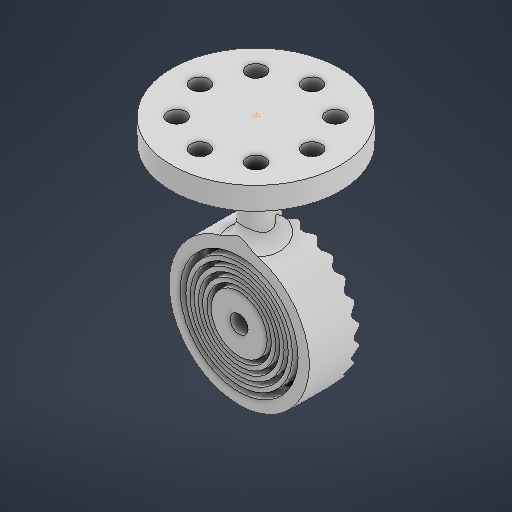
# Autodesk Inventor part: ParteA
Saved by Autodesk Inventor 2027.1 (Build 311270010, 270A)
## iProperties
Created: 2026-09-14
Part Number: ParteA
Material: Genérico
Document SubType Name: Modeling
Designer: felip
Density: 1 g/cm^3
Appearance: Valor por defecto
Author: felip
Autodesk Inventor part; units mm, degrees
sketch "Boceto1" plane through (0, 0, 0) normal (0, 0, 1) x (1, 0, 0)
  circle A0 centre (0, 0) radius 25
  circle A1 centre (0, 0) radius 3.175
  dimension "d0" = 50
  dimension "d1" = 6.35
  constraints: 2 centre point, 2 coincident
  measures "d0" diameter of A0
  measures "d1" diameter of A1
extrude "Extrusión1" add sketch "Boceto1" along normal blind 12 and the other way blind 6
ref_plane "Plano de trabajo1" through (0, 25, 0) normal (0, 1, 0) x (-1, 0, 0)
sketch "Boceto3" plane through (0, 25, 0) normal (0, 1, 0) x (-1, 0, 0)
  line L0 (3.175, -6) -> (-3.175, -6) projected
  line L1 (2.784, -6) -> (-2.784, -6)
  line L2 (0, -6) -> (0, -4) construction
  line L3 (0.5, -4) -> (-0.5, -4)
  line L4 (2.784, -6) -> (0.5, -4)
  line L5 (-0.5, -4) -> (-2.784, -6)
  point P0 (0, 0)
  dimension "d16" = 5.568
  dimension "d17" = 2
  dimension "d18" = 1
  constraints: 10 end point, 3 midpoint, 1 horizontal, 1 point on line, 1 vertical
  measures "d16" distance of L1.start L1.end
  measures "d17" distance of L2.start L2.end
  measures "d18" distance of L3.start L3.end
loft "Solevación2" cut profiles "Boceto3" section 2 point at (0, 0, -6)
ref_plane "Plano de trabajo3" through (0, 3.1, 0) normal (0, 1, 0) x (-1, 0, 0)
sketch "Boceto6" plane through (0, 3.1, 0) normal (0, 1, 0) x (-1, 0, 0)
  line L0 (0.3514, -6) -> (-0.3514, -6)
  line L1 (0, -6) -> (0, -4) construction
  line L2 (0.0635, -4) -> (-0.0635, -4)
  line L3 (0.3514, -6) -> (0.0635, -4)
  line L4 (-0.0635, -4) -> (-0.3514, -6)
  point P0 (0, 0)
  point P1 (0, -6)
  point P2 (0.0635, -5.7461)
  dimension "d48" = 2
  dimension "d49" = 0.127
  constraints: 10 end point, 2 midpoint, 1 vertical
  measures "d48" distance of L1.start L1.end
  measures "d49" distance of L2.start L2.end
loft "Solevación4" cut profiles "Boceto3", "Boceto6"
pattern_circular "Patrón circular4" count 24 over 360 about axis through (0, 0, 0) along (0, 0, 1) of "Solevación4"
ref_plane "Plano de trabajo4" through (0, 0, 6) normal (0, 0, 1) x (1, 0, 0)
sketch "Boceto8" plane through (0, 0, 6) normal (0, 0, 1) x (1, 0, 0)
  line L0 (0, 0) -> (0, 20)
  line L1 (0, 20) -> (0, 45)
  dimension "d63" = 20
  dimension "d64" = 25
  constraints: 4 end point, 1 point on line, 1 vertical
  measures "d63" distance of L0.start L0.end
  measures "d64" distance of L0.end L1.end
sketch "Boceto9" plane through (0, 0, 0) normal (0, 1, 0) x (-1, 0, 0)
  line L0 (0, 0) -> (0, 6) construction
  circle A0 centre (0, 6) radius 5
  dimension "d65" = 6
  dimension "d66" = 10
  constraints: 2 end point, 1 centre point, 1 coincident, 1 vertical
  measures "d65" distance of L0.start L0.end
  measures "d66" diameter of A0
sweep "Barrido1" add profiles "Boceto9" path "Boceto8"
fillet "Empalme1" radius 5 1 edges at (5, 24.4949, 6)
sketch "Boceto10" plane through (0, 45, 6) normal (0, 1, 0) x (1, 0, 0)
  circle A0 centre (0, 0) radius 7.5
  circle A1 centre (0, 0) radius 3
  point P0 (0, 6)
  dimension "d70" = 15
  dimension "d71" = 6
  constraints: 2 centre point, 1 coincident
  measures "d70" diameter of A0
  measures "d71" diameter of A1
extrude "Extrusión5" cut sketch "Boceto10" along normal blind 10 and the other way blind 24 contours A1
extrude "Extrusión6" add sketch "Boceto10" along normal blind 10
fillet "Empalme2" radius 3 1 edges at (5, 45, 6)
sketch "Boceto12" plane through (0, 55, 6) normal (0, 1, 0) x (1, 0, 0)
  circle A0 centre (0, 0) radius 3 construction
  circle A1 centre (0, 0) radius 20 construction
  line L0 (0, 0) -> (14.1421, 14.1421) construction
  line L1 (0, 0) -> (20, 0) construction
  circle A2 centre (14.1421, 14.1421) radius 3.25
  circle A3 centre (0, 20) radius 3.25
  circle A4 centre (-14.1421, 14.1421) radius 3.25
  circle A5 centre (-20, 0) radius 3.25
  circle A6 centre (-14.1421, -14.1421) radius 3.25
  circle A7 centre (0, -20) radius 3.25
  circle A8 centre (14.1421, -14.1421) radius 3.25
  circle A9 centre (20, 0) radius 3.25
  circle A10 centre (0, 0) radius 30
  point P0 (0, 6)
  dimension "d79" = 40
  dimension "d80" = 45
  dimension "d81" = 6.5
  dimension "d84" = 360
  dimension "d86" = 60
  constraints: 9 centre point, 4 end point, 3 coincident, 1 equal length, 1 horizontal, 20 other
  measures "d80" angle of L1 L0
  measures "d81" diameter of A2
  measures "d86" diameter of A10
extrude "Extrusión7" add sketch "Boceto12" along normal blind 6 and the other way blind 2
extrude "Extrusión8" cut sketch "Boceto1" along normal mid plane 40 contours A1
ref_plane "Plano de trabajo5" through (0, 61, 6) normal (0, 1, 0) x (1, 0, 0)
sketch "Boceto13" plane through (0, 53, 6) normal (0, -1, 0) x (1, 0, 0)
  line L0 (-16.75, -3.25) -> (16.75, -3.25)
  line L1 (16.75, -3.25) -> (16.75, 3.25)
  line L2 (16.75, 3.25) -> (-16.75, 3.25)
  line L3 (-16.75, 3.25) -> (-16.75, -3.25)
  line L4 (-16.75, -3.25) -> (16.75, 3.25) construction
  line L5 (16.75, -3.25) -> (-16.75, 3.25) construction
  line L6 (-3.25, 16.75) -> (-3.25, -16.75)
  line L7 (-3.25, -16.75) -> (3.25, -16.75)
  line L8 (3.25, -16.75) -> (3.25, 16.75)
  line L9 (3.25, 16.75) -> (-3.25, 16.75)
  line L10 (-3.25, 16.75) -> (3.25, -16.75) construction
  line L11 (-3.25, -16.75) -> (3.25, 16.75) construction
  line L12 (3.25, 16.75) -> (3.25, 20)
  arc A0 (0, 16.75) -> (3.25, 20) centre (0, 20) ccw
  line L13 (-16.75, 3.25) -> (-20, 3.25)
  arc A1 (-16.75, 0) -> (-20, 3.25) centre (-20, 0) ccw
  line L14 (-3.25, -16.75) -> (-3.25, -20)
  arc A2 (0, -16.75) -> (-3.25, -20) centre (0, -20) ccw
  line L15 (16.75, -3.25) -> (20, -3.25)
  arc A3 (16.75, 0) -> (20, -3.25) centre (20, 0) ccw
  line L16 (-3.25, 16.75) -> (-3.25, 20)
  arc A4 (-3.25, 20) -> (0, 16.75) centre (0, 20) ccw
  arc A5 (-20, -3.25) -> (-16.75, 0) centre (-20, 0) ccw
  line L17 (-16.75, -3.25) -> (-20, -3.25)
  arc A6 (3.25, -20) -> (0, -16.75) centre (0, -20) ccw
  line L18 (3.25, -16.75) -> (3.25, -20)
  arc A7 (20, 3.25) -> (16.75, 0) centre (20, 0) ccw
  line L19 (16.75, 3.25) -> (20, 3.25)
  point P0 (0, -6)
  point P1 (0, 0)
  point P2 (0, 0)
  dimension "d96" = 360
  dimension "d100" = 360
  constraints: 40 end point, 16 point on circle, 8 centre point, 6 midpoint, 5 parallel, 2 coincident, 2 perpendicular, 1 horizontal, 50 other
sketch "Boceto14" plane through (0, 0, 12) normal (0, 0, 1) x (1, 0, 0)
  circle A0 centre (0, 0) radius 10
  circle A1 centre (0, 0) radius 11.5
  circle A2 centre (0, 0) radius 13
  circle A3 centre (0, 0) radius 14.5
  circle A4 centre (0, 0) radius 16
  circle A5 centre (0, 0) radius 17.5
  circle A6 centre (0, 0) radius 19
  circle A7 centre (0, 0) radius 21
  dimension "d102" = 20
  dimension "d103" = 23
  dimension "d104" = 26
  dimension "d105" = 29
  dimension "d106" = 32
  dimension "d107" = 35
  dimension "d108" = 38
  dimension "d109" = 42
  constraints: 8 centre point, 8 coincident
  measures "d102" diameter of A0
  measures "d103" diameter of A1
  measures "d104" diameter of A2
  measures "d105" diameter of A3
  measures "d106" diameter of A4
  measures "d107" diameter of A5
  measures "d108" diameter of A6
  measures "d109" diameter of A7
extrude "Extrusión9" cut sketch "Boceto14" against normal blind 9
